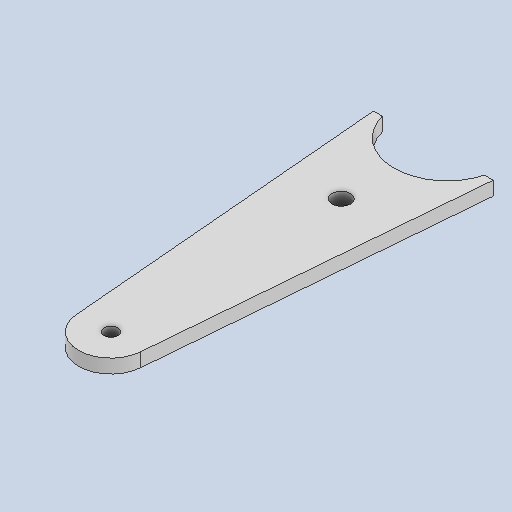
# Autodesk Inventor part: manivela_p2
Saved by Autodesk Inventor 2025.2 (Build 292293000, 293)
## iProperties
Created: 2025-05-07
Part Number: manivela_p2
Material: Generic
Document SubType Name: Modeling
Designer: laura
Density: 1 g/cm^3
Appearance: Default
Author: laura
Autodesk Inventor part; units mm, degrees
ref_plane "YZ Plane" through (0, 0, 0) normal (1, 0, 0) x (0, 1, 0)
ref_plane "XZ Plane" through (0, 0, 0) normal (0, 1, 0) x (-1, 0, 0)
ref_plane "XY Plane" through (0, 0, 0) normal (0, 0, 1) x (1, 0, 0)
sketch "Sketch1" plane through (0, 0, 0) normal (0, 1, 0) x (-1, 0, 0)
  line L0 (6.9746, 35.5953) -> (13, -35)
  line L1 (-13, -35) -> (-6.9746, 35.5953)
  arc A0 (6.9746, 35.5953) -> (-6.9746, 35.5953) centre (0, 35) ccw
  line L2 (13, -35) -> (-13, -35)
  line L3 (0, 35) -> (0, -35)
  point P0 (0, 0)
  point P1 (0, 0)
  point P2 (0, 0)
  dimension "d2" = 7
  dimension "d5" = 26
  dimension "d6" = 70
  constraints: 8 end point, 2 coincident, 2 midpoint, 2 point on circle, 2 tangent, 1 centre point, 1 horizontal, 1 vertical
  measures "d2" radius of A0
  measures "d5" diameter of L0.end L3
  measures "d6" distance of L3.end L3.start
extrude "Extrusion1" add sketch "Sketch1" along normal blind 3
sketch "Sketch2" plane through (0, 3, 0) normal (0, 1, 0) x (1, 0, 0)
  circle A0 centre (0, 38) radius 11.5
  line L0 (0, 0) -> (0, 38) construction
  line L1 (0, 0) -> (0, -42) construction
  arc A1 (-6.9746, -35.5953) -> (6.9746, -35.5953) centre (0, -35) ccw construction
  circle A2 centre (0, -35) radius 1.5
  circle A3 centre (0, 15) radius 2
  line L2 (13, 35) -> (-13, 35) projected
  dimension "d9" = 23
  dimension "d10" = 38
  dimension "d13" = 3
  dimension "d14" = 20
  dimension "d15" = 4
  constraints: 4 end point, 3 centre point, 2 coincident, 1 point on circle, 1 point on line, 1 vertical
  measures "d9" diameter of A0
  measures "d10" distance of L0.start L0.end
  measures "d13" diameter of A2
  measures "d14" distance from line of L2 A3.centre
  measures "d15" diameter of A3
extrude "Extrusion2" cut sketch "Sketch2" against normal through all contours A0 L2 | L2 A0
extrude "Extrusion3" cut sketch "Sketch2" against normal through all contours A2 | A3
body "Solid1"
